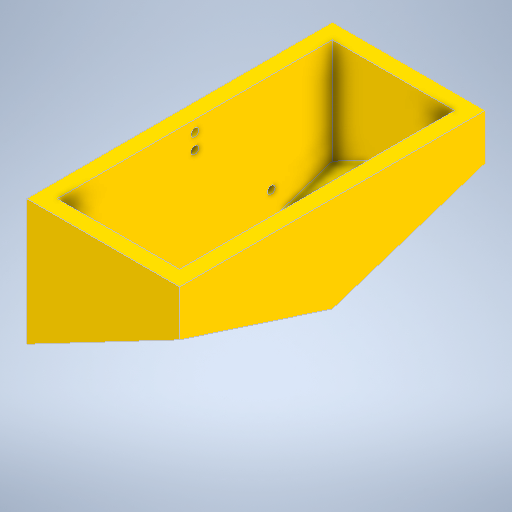
# Autodesk Inventor part: BOW DESIGN
Saved by Autodesk Inventor 2026.2 (Build 302298000, 298)
## iProperties
Created: 2026-07-20
Part Number: BOW DESIGN
Material: PLA
Document SubType Name: Modeling
Designer: Taiye Raji
Density: 0.3959 g/cm^3
Appearance: Generic
Mass: 1113.39 g
Surface Area: 4712.46 cm^2
Volume: 4453.58 cm^3
Author: Taiye Raji
Autodesk Inventor part; units mm, degrees
ref_plane "XZ Plane" through (0, 0, 0) normal (0, 1, 0) x (-1, 0, 0)
ref_plane "XY Plane" through (0, 0, 0) normal (0, 0, 1) x (1, 0, 0)
sketch "Sketch12" plane through (0, 0, 0) normal (1, 0, 0) x (0, 1, 0)
  line L0 (0, -200) -> (0, 200)
  line L1 (0, -200) -> (-165.0161, -200)
  line L2 (-165.0161, -200) -> (-230, 0)
  line L3 (0, 200) -> (-165.0161, 200)
  line L4 (-165.0161, 200) -> (-230, 0)
  point P0 (0, 0)
  dimension "d51" = 400
  dimension "d52" = 108
  dimension "d53" = 230
  constraints: 10 end point, 2 horizontal, 1 equal length, 1 horizontal alignment, 1 midpoint, 1 vertical
  measures "d51" distance of L0.start L0.end
  measures "d52" angle of L2 L1
  measures "d53" distance from line of L2.end L0
ref_plane "Work Plane1" through (200, 0, 0) normal (1, 0, 0) x (0, 1, 0)
sketch "Sketch14" plane through (200, 0, 0) normal (1, 0, 0) x (0, 1, 0)
  line L0 (0, -200) -> (0, 200)
  line L1 (0, 200) -> (-60.0161, 200)
  line L2 (-60.0161, 200) -> (-125, 0)
  line L3 (-125, 0) -> (-60.0161, -200)
  line L4 (-60.0161, -200) -> (0, -200)
  point P0 (0, 0)
  point P1 (0, 0)
  dimension "d59" = 108
  dimension "d60" = 400
  dimension "d61" = 125
  constraints: 10 end point, 2 horizontal, 1 coincident, 1 horizontal alignment, 1 midpoint, 1 parallel, 1 vertical
  measures "d59" angle of L3 L4
  measures "d60" distance of L0.start L0.end
  measures "d61" distance of L2.end point (0, 0)
loft "Loft1" add profiles "Sketch14", "Sketch12"
shell "Shell5" thickness 20 removed faces 1 at (133.3333, 0, 66.6667)
sketch "Sketch15" plane through (0, -165.0161, -200) normal (-1, 0, 0) x (0, 0, 1)
  circle A0 centre (200, 130.0161) radius 5
  line L0 (400, 165.0161) -> (0, 165.0161) projected
  circle A1 centre (100, 35.0161) radius 5
  line L1 (400, 0) -> (400, 165.0161) projected
  line L2 (0, 0) -> (400, 0) construction
  line L3 (200, -64.9839) -> (400, 0) projected
  line L4 (200, 165.0161) -> (200, -64.9839) construction
  circle A2 centre (300, 35.0161) radius 5
  circle A3 centre (200, 150.0161) radius 5
  dimension "d67" = 35
  dimension "d68" = 10
  dimension "d69" = 100
  dimension "d71" = 100
  dimension "d72" = 100
  dimension "d73" = 230
  dimension "d74" = 400
  dimension "d77" = 15
  constraints: 4 centre point, 4 end point, 2 equal radius, 1 horizontal, 1 midpoint, 1 point on line, 1 symmetric about line, 1 vertical, 1 vertical alignment, 1 other
  measures "d67" distance from line of A0.centre L0
  measures "d68" diameter of A0
  measures "d69" horizontal distance of A1.centre L4.start
  measures "d71" horizontal distance of A1.centre L3.start
  measures "d72" distance from line of L4 A1.centre
  measures "d73" distance of L4.start L3.start
  measures "d74" distance of L2.start L1.start
  measures "d77" distance from line of A3.centre L0
extrude "Extrusion12" cut sketch "Sketch15" against normal blind 20
body "Solid5"
